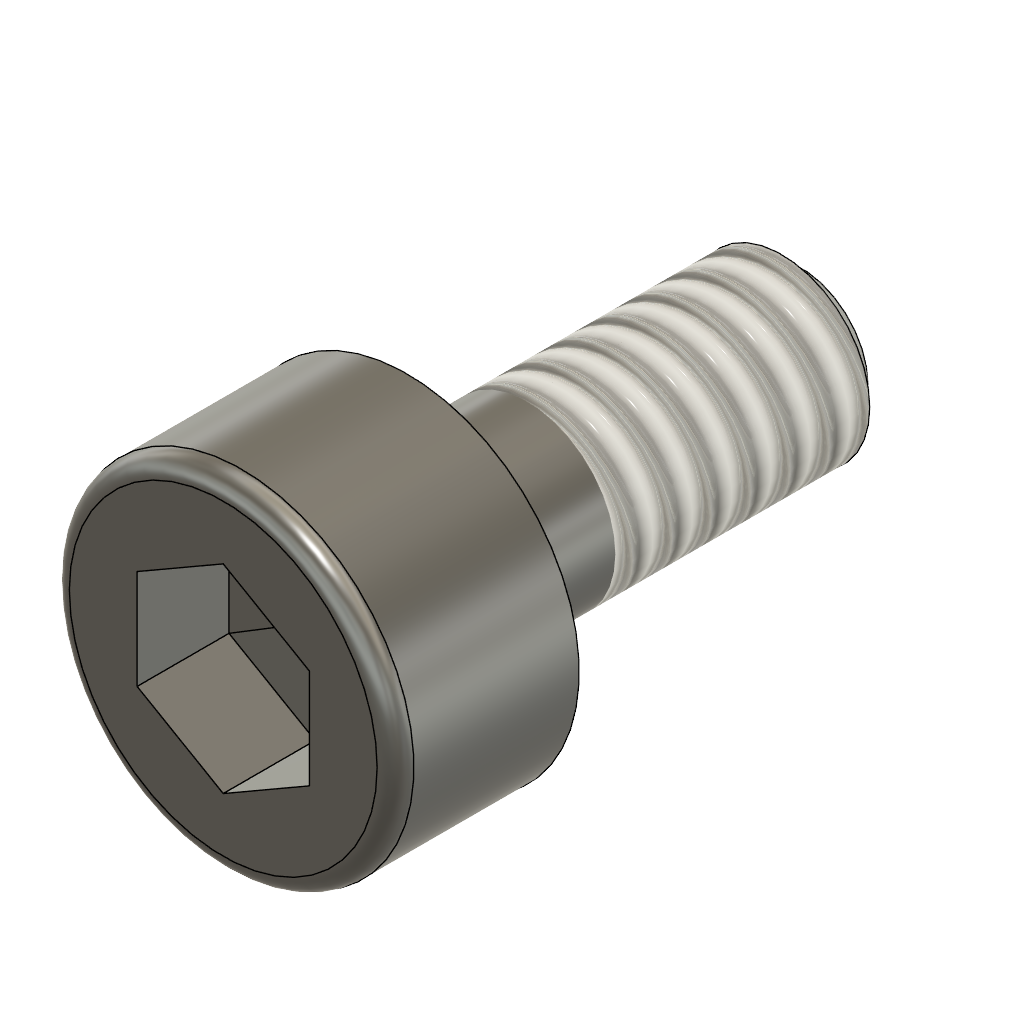
crazy car full (Autodesk Fusion 360 archive; units mm, degrees)
design "Zylinderschraube mit gestanztem Innensechskant ASME B18.3.1M - M1.4x0.3 x 3 Stahlklasse 2 Einfach"
description: Zylinderschraube mit gestanztem Innensechskant ASME B18.3.1M - M1.4x0.3 x 3
part number: BSHCS ASME B18.3.1M - M1.4x0.3 x 3 Stahlklasse 2 Einfach
Autodesk Fusion 360 part; units mm, degrees
sketch "Sketch1" plane through (0, 0, 0) normal (0, 1, 0) x (1, 0, 0)
  line L0 (-0.7, 0) -> (-0.7, 3)
  line L1 (-0.7, 3) -> (0, 3)
  line L2 (0, 3) -> (0, -1.4)
  line L3 (-0.7, 0) -> (-1.3125, 0)
  line L4 (-1.3125, 0) -> (-1.3125, -1.4)
  line L5 (-1.3125, -1.4) -> (0, -1.4)
  dimension "d101" = 3
  dimension "d102" = 1.4
  dimension "d109" = 2.625
  dimension "d110" = 1.4
  constraint perpendicular L0 L1
  constraint collinear origin L1.end L2.end
  constraint perpendicular L0 L3
  constraint coincident origin L3
  constraint vertical L2
  constraint coincident L2 L5.end
  constraint perpendicular L2 L5
  measures "d101" distance of origin L1
  measures "d102" distance of L3.end L5
revolve "Revolve1" add sketch "Sketch1" angle 360 about axis through (0, 0, -3) along (0, 0, 1)
ref_plane "WorkPlane1" through (0, 0, 1.4) normal (0, 0, 1) x (1, 0, 0)
sketch "Sketch6" plane through (0, 0, 1.4) normal (0, 0, 1) x (1, 0, 0)
  line L0 (0, -0.7578) -> (0.6563, -0.3789)
  line L1 (0.6563, -0.3789) -> (0.6563, 0.3789)
  line L2 (0.6563, 0.3789) -> (0, 0.7578)
  line L3 (0, 0.7578) -> (-0.6562, 0.3789)
  line L4 (-0.6562, 0.3789) -> (-0.6563, -0.3789)
  line L5 (-0.6563, -0.3789) -> (0, -0.7578)
  dimension "d111" = 1.3125
  constraint vertical L1
  measures "d111" distance of L1 L4
extrude "Extrude1" cut sketch "Sketch6" against normal blind 0.7
extrude "Extrude2" cut 1 faces at (0, -0.2526, 0.7) along direction (0, 0, -1) blind 0.7 draft -85
thread "Thread3" "ANSI Metric M Profile 1.4 M1.4x0.3 M1.4x0.3 4g6g" major diameter 1.3455 minor diameter 1.0193 pitch 0.3 angle 60 resizes the face on face at (-0.6965, 0.0697, -2) from (0, 0, -0.9147) to (0, 0, -3)
fillet "Fillet4" radius 0.14 1 edges at (-1.2237, 0.4746, 1.4)
sketch "Sketch7" plane through (0, 0, 0) normal (0, 1, 0) x (1, 0, 0)
  line L0 (-0.714, 3) -> (-0.714, 2.816)
  line L1 (-0.714, 2.816) -> (-0.5121, 3)
  line L2 (0, 3) -> (0, -1.4)
  line L3 (-0.714, 3) -> (0, 3)
  dimension "d104" = 0.5121
  dimension "d105" = 0.714
  dimension "d106" = 0.184
  constraint coincident L2.start L3.end
  constraint perpendicular L2 L3
  constraint coincident L1.end L3
  constraint perpendicular L0 L3
  measures "d104" distance of L1.end L2
  measures "d105" distance of L0 L2.start
  measures "d106" distance of L0.end L3
revolve "Revolve3" cut sketch "Sketch7" angle 360 about axis through (0, 0, 1.75) along (0, 0, 1)
equation "adsk_nomlen = 3.00 mm"
equation "adsk_headh = 1.40 mm"
equation "adsk_headdia = 2.625 mm"
equation "adsk_nomdia = 1.40 mm"
equation "adsk_philwidth = 1.3125 mm"
equation "d31 = -adsk_phildepth"
equation "adsk_phildepth = 0.70 mm"
equation "d71 = adsk_headh"
equation "d76 = -adsk_phildepth"
equation "adsk_thrlen = 2.0852925 mm"
equation "d86 = adsk_nomdia * 0.1"
equation "adsk_startlen = 0.184035 mm"
equation "adsk_endpointdia = 1.0242619 mm"
equation "d101 = adsk_nomlen"
equation "d102 = adsk_headh"
equation "d104 = adsk_endpointdia / 2"
equation "d105 = adsk_nomdia * 0.51"
equation "d106 = adsk_startlen"
equation "d108 = min(adsk_thrlen; adsk_nomlen - 0.001 mm)"
equation "d109 = adsk_headdia"
equation "d110 = adsk_nomdia"
equation "d111 = adsk_philwidth"

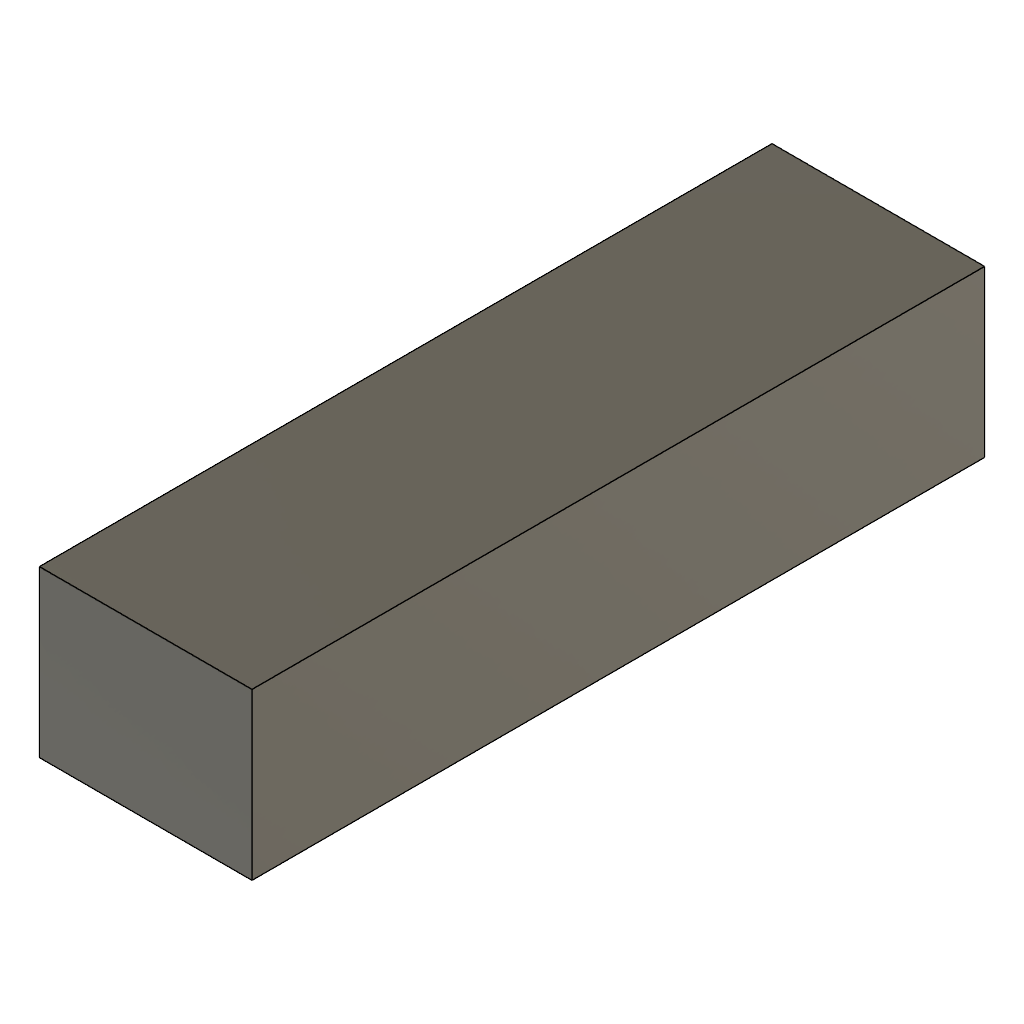
design "Akku"
Autodesk Fusion 360 part; units mm, degrees
sketch "Skizze1" plane through (0, 0, 0) normal (0, 0, 1) x (1, 0, 0)
  line L0 (9, 31) -> (-9, 31)
  line L1 (-9, 31) -> (-9, -31)
  line L2 (-9, -31) -> (9, -31)
  line L3 (9, -31) -> (9, 31)
  line L4 (9, 31) -> (-9, -31) construction
  line L5 (-9, 31) -> (9, -31) construction
  dimension "d1" = 18
  dimension "d2" = 62
  constraint horizontal L0
  constraint perpendicular L0 L1
  constraint parallel L0 L2
  constraint parallel L1 L3
  constraint coincident L4 origin
  constraint coincident L5 origin
  measures "d1" distance of L1.end L2.end
  measures "d2" distance of L0.end L1.end
extrude "Extrusion1" add sketch "Skizze1" along normal blind 14

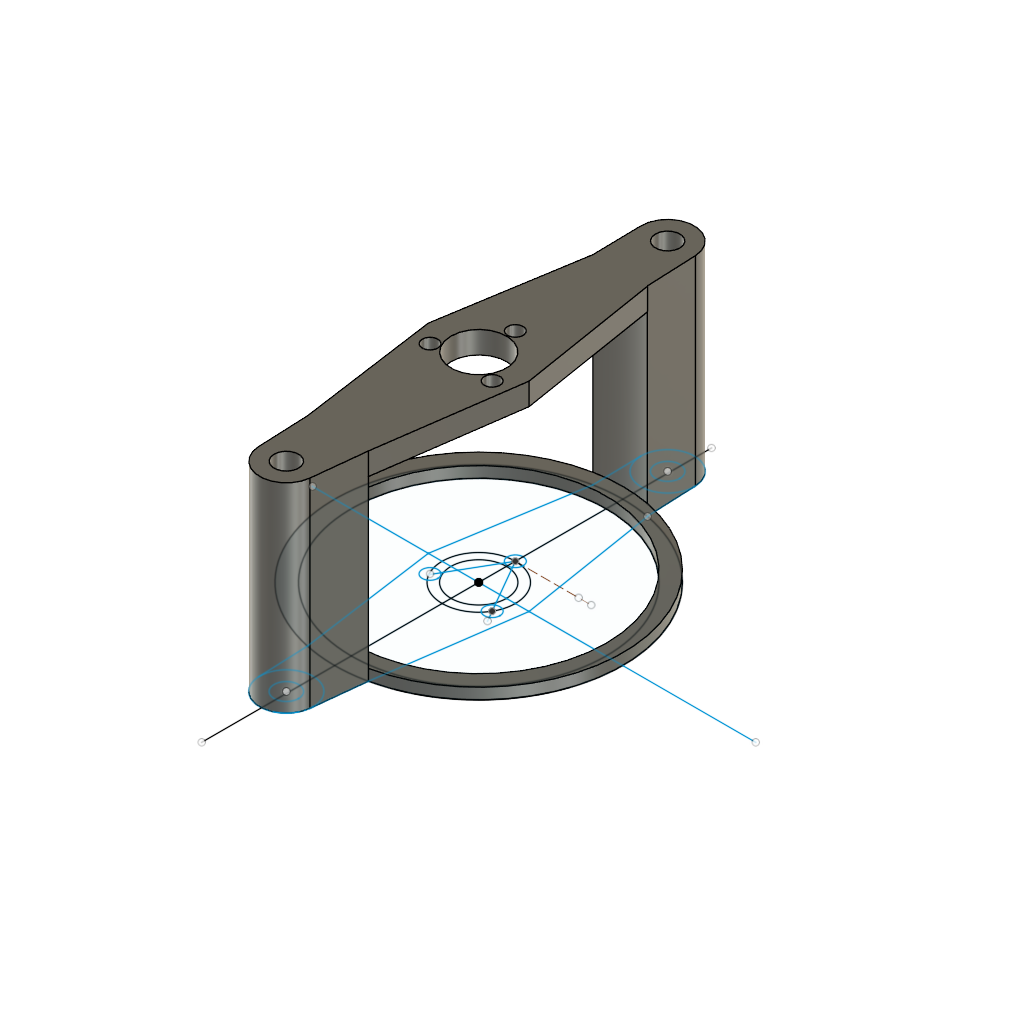
design "impeller halter"
Autodesk Fusion 360 part; units mm, degrees
sketch "Skizze1" plane through (0, 0, 0) normal (0, 0, 1) x (1, 0, 0)
  circle A0 centre (0, 0) radius 13
  circle A1 centre (-0.1535, 17.1993) radius 1.1
  line L0 (-15, -0.0052) -> (25, -0.0052)
  circle A2 centre (-0.1535, -17.2098) radius 1.1
  circle A3 centre (-0.1535, 17.1993) radius 2.4
  circle A4 centre (-0.1535, -17.2098) radius 2.4
  circle A5 centre (0, 0) radius 11.5
  line L1 (-2.5531, 17.1534) -> (-2.469, 12.7634)
  line L2 (2.2442, 17.3039) -> (2.4421, 12.7686)
  line L3 (-2.5512, -17.3144) -> (-2.7523, -12.7053)
  line L4 (2.2323, -17.4701) -> (2.7523, -12.7053)
  circle A6 centre (0, 0) radius 3.3
  circle A7 centre (0, 0) radius 2.5
  circle A8 centre (0, 3.3) radius 0.7
  line L5 (0, 3.3) -> (3.4254, -2.633)
  line L6 (0, 3.3) -> (6.8508, 3.3) construction
  circle A9 centre (2.8579, -1.65) radius 0.7
  line L7 (0, 3.3) -> (-2.8579, -1.65)
  line L8 (0, 3.3) -> (5.7158, 3.3) construction
  circle A10 centre (-2.8579, -1.5392) radius 0.7
  line L9 (-2.469, 12.7634) -> (-4.5435, -0.0052)
  line L10 (-4.5435, -0.0052) -> (-2.7523, -12.7053)
  line L11 (0, 21) -> (0, -25)
  line L12 (2.469, 12.7634) -> (4.5435, -0.0052)
  line L13 (4.5435, -0.0052) -> (2.7523, -12.7053)
  dimension "d1" = 26
  dimension "d2" = 2.2
  dimension "d3" = 17.2
  dimension "d4" = 4.8
  dimension "d5" = 4.8
  dimension "d6" = 23
  dimension "d11" = 6.6
  dimension "d12" = 5
  dimension "d13" = 1.4
  dimension "d14" = 60
  dimension "d15" = 1.4
  dimension "d16" = 120
  dimension "d17" = 1.4
  constraint coincident A0.centre A5.centre
  constraint horizontal L0
  constraint symmetric A1 L0 A2
  constraint concentric A1 A3
  constraint concentric A2 A4
  constraint concentric A0 A5
  constraint coincident A3 L1.start
  constraint coincident A0 L1.end
  constraint tangent A3 L1
  constraint coincident A3 L2.start
  constraint coincident A0 L2.end
  constraint tangent A3 L2
  constraint coincident A0 L3.end
  constraint parallel L2 L3
  constraint coincident A4 L4.start
  constraint coincident A0 L4.end
  constraint tangent A4 L4
  constraint coincident A4 L3.start
  constraint tangent A4 L3
  constraint concentric A0 A6
  constraint coincident A6 A8.centre
  constraint horizontal L6
  constraint coincident A8.centre L5.start
  constraint coincident L5 A9.centre
  constraint coincident A6 A9.centre
  constraint horizontal L8
  constraint coincident A6 L7.end
  constraint coincident L0 L9.end
  constraint vertical L11
  constraint symmetric L1.end L11 L12.start
  constraint symmetric L3.end L4.end L11
  constraint symmetric L9.end L11 L12.end
  measures "d1" diameter of A0
  measures "d2" diameter of A1
  measures "d3" distance of A0.centre A1.centre
  measures "d4" diameter of A3
  measures "d5" diameter of A4
  measures "d6" diameter of A5
  measures "d11" diameter of A6
  measures "d12" diameter of A7
  measures "d13" diameter of A8
  measures "d14" angle of L5 L6
  measures "d15" diameter of A9
  measures "d16" angle of L7 L8
  measures "d17" diameter of A10
extrude "Extrusion1" add sketch "Skizze1" along normal blind 1 contours A0 L0 A5 L12 | A0 A5 L11 L12 | A0 L0 A5 L13 | A0 A5 L11 L13 | A0 A5 L9 L11 | A0 A5 L10 L11 | A0 L0 A5 L9 | A0 L0 A5 L10
extrude "Extrusion2" add sketch "Skizze1" along normal blind 18 contours A0 A3 L2 L11 | A0 A4 L4 L11 | A0 A3 L1 L11 | A1 A3 L11 | A0 A4 L3 L11 | A2 A4 L11 | A1 A3 L11 | A2 A4 L11
extrude "Extrusion3" add sketch "Skizze1" along normal blind 2 from surface at 16 contours A0 A5 L11 L12 | L0 A5 A6 A8 L11 L12 | A0 A5 L11 L13 | A0 A5 L9 L11 | L0 A5 A6 A8 L9 L11 | L0 A5 A6 A9 L11 L13 | A0 A5 L10 L11 | L0 A6 A7 L5 A9 | L0 A6 A7 A8 L5 | L0 A5 A6 A10 L10 L11 | L0 A6 A7 A8 L7 | A6 A7 L5 A9 L11 | A6 A7 L7 A10 L11 | L0 A6 A7 L7 A10 | A7 A8 L7 L11 | A7 A8 L5 L11
equation "d9 = 15 mm + 14 mm - 8 mm - 2 mm - 1 mm"
equation "d18 = 24.00 mm - 8 mm"

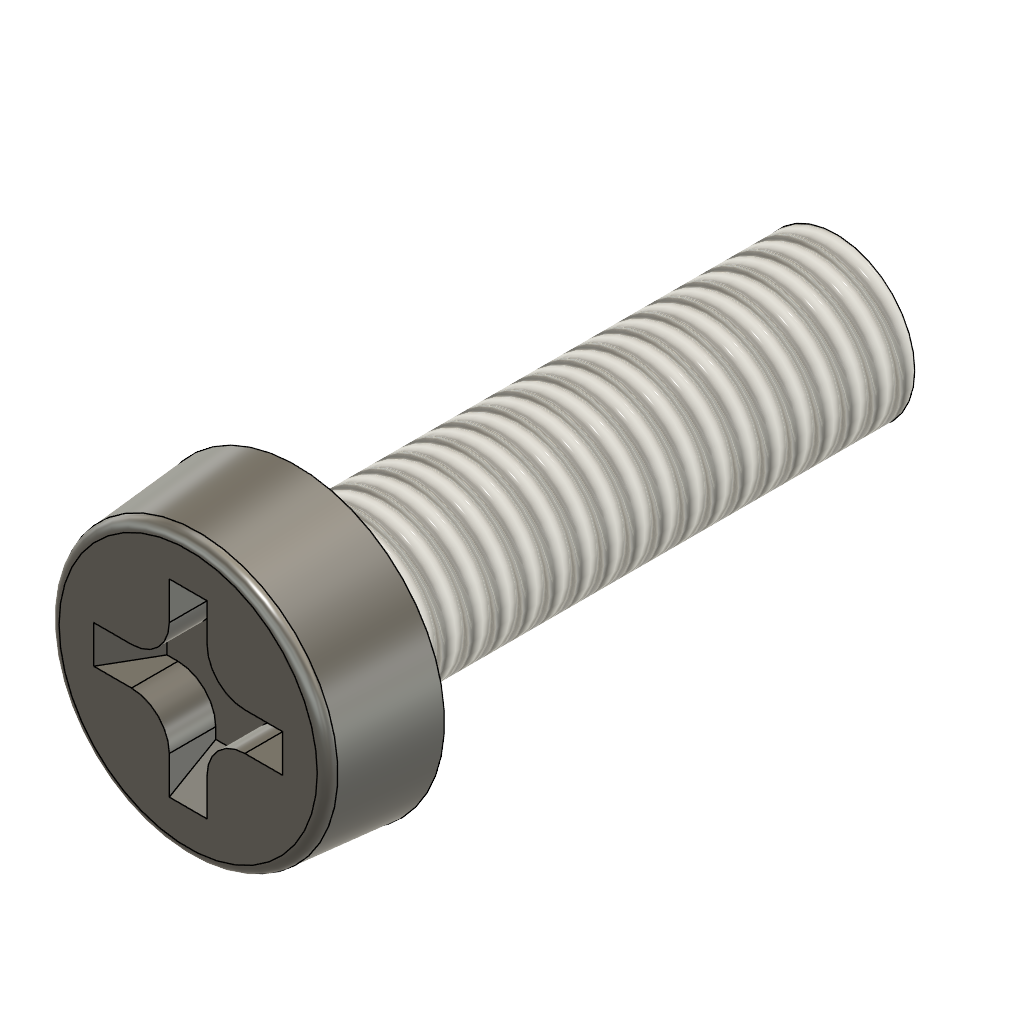
design "Zylinderschraube NS-EN ISO 7048 - M3 x 10 - H Stahl 4.6 Einfach"
description: Zylinderschraube NS-EN ISO 7048 - M3 x 10 - H
part number: NS-EN ISO 7048 - H - M3 x 10 Stahl 4.6 Einfach
Autodesk Fusion 360 part; units mm, degrees
sketch "Sketch1" plane through (0, 0, 0) normal (0, 1, 0) x (1, 0, 0)
  line L0 (0, -2) -> (0, 10)
  line L1 (-2.75, 0) -> (-2.575, -2)
  line L2 (-2.75, 0) -> (-1.325, 0)
  line L3 (0, 10) -> (-1.5, 10)
  line L4 (-1.5, 10) -> (-1.5, 1)
  line L5 (-1.5, 1) -> (-1.325, 0.3469)
  line L6 (-1.325, 0.3469) -> (-1.325, 0)
  line L7 (0, -2) -> (-2.575, -2)
  dimension "d13" = 5
  dimension "d14" = 5.5
  dimension "d18" = 3
  dimension "d56" = 10
  dimension "d65" = 15
  dimension "d67" = 2
  dimension "d71" = 2.65
  dimension "d77" = 1
  constraint vertical L0
  constraint coincident origin L0
  constraint coincident origin L2
  constraint perpendicular L0 L3
  constraint coincident L2.end L6.end
  constraint perpendicular L0 L7
  measures "d13" angle of L0 L1
  measures "d56" distance of L2 L3
  measures "d65" angle of L5 L6
  measures "d67" distance of L1.start L7
  measures "d77" distance of L2 L4.end
revolve "Revolve1" add sketch "Sketch1" angle 360 about axis through (0, 0, 2) along (0, 0, -1) makes body 1
fillet "Fillet3" radius 0.2 1 edges at (-2.4008, 0.9312, 2) on bodies 1
fillet "Fillet2" radius 0.1 1 edges at (-1.2353, 0.4791, 0) on bodies 1
sketch "Sketch2" plane through (0, 0, 2) normal (0, 0, 1) x (1, 0, 0)
  line L0 (-0.35, 0.35) -> (-1.75, 0.35)
  line L1 (-1.75, 0.35) -> (-1.75, -0.35)
  line L2 (-1.75, -0.35) -> (-0.35, -0.35)
  line L3 (-0.35, -0.35) -> (-0.35, -1.75)
  line L4 (-0.35, -1.75) -> (0.35, -1.75)
  line L5 (0.35, -1.75) -> (0.35, -0.35)
  line L6 (0.35, -0.35) -> (1.75, -0.35)
  line L7 (1.75, -0.35) -> (1.75, 0.35)
  line L8 (1.75, 0.35) -> (0.35, 0.35)
  line L9 (0.35, 0.35) -> (0.35, 1.75)
  line L10 (0.35, 1.75) -> (-0.35, 1.75)
  line L11 (-0.35, 1.75) -> (-0.35, 0.35)
  dimension "d81" = 360
  dimension "d83" = 0.7
  dimension "d84" = 3.5
  constraint horizontal L0
  constraint perpendicular L0 L1
  constraint vertical L0.start L2.end
  constraint coincident L2.end L3.start
  measures "d83" distance of L0 L2
  measures "d84" distance of L1 L6.end
extrude "Extrude1" add sketch "Sketch2" against normal blind 0.86 separate body makes body 2
draft "Draft1" angle -30 neutral plane through (0, 0, 2) pull (0, 0, 1) 4 faces at (1.75, -0.1167, 1.7133) (0.1167, 1.75, 1.7133) (-1.75, 0.1167, 1.7133) (-0.1167, -1.75, 1.7133) on bodies 2
fillet "Fillet1" radius 0.7 4 edges at (-0.35, 0.35, 1.57) (-0.35, -0.35, 1.57) (0.35, -0.35, 1.57) (0.35, 0.35, 1.57) on bodies 2
combine "Combine1" operation cut target body 1 tool bodies 2
thread "Thread3" "ISO Metric profile 3.0 M3x0.5 M3x0.5 6g" major diameter 2.927 minor diameter 2.3555 pitch 0.5 angle 60 resizes the face on face at (-1.4981, -0.0748, -7) on bodies 1
equation "adsk_nomdia = 3.00 mm"
equation "adsk_nomlen = 10.00 mm"
equation "adsk_headdia = 5.50 mm"
equation "adsk_phildia = 3.50 mm"
equation "adsk_midfillet = 0.10 mm"
equation "adsk_phildepth = 0.86 mm"
equation "adsk_shnklen = 1.00 mm"
equation "adsk_thrang = 15 deg"
equation "adsk_headang = 5 deg"
equation "d13 = adsk_headang"
equation "d14 = adsk_headdia"
equation "d18 = adsk_nomdia"
equation "adsk_philwidth = 0.70 mm"
equation "d43 = -adsk_phildepth"
equation "d52 = adsk_midfillet"
equation "d56 = adsk_nomlen"
equation "d65 = adsk_thrang"
equation "d67 = adsk_headh"
equation "adsk_headh = 2.00 mm"
equation "adsk_pitch1 = 0.50 mm"
equation "adsk_shnkdia = adsk_nomdia - 0.7 * adsk_pitch1"
equation "d71 = adsk_shnkdia"
equation "adsk_headtoprad = adsk_headh * 0.1"
equation "d76 = adsk_headtoprad"
equation "d77 = adsk_shnklen"
equation "d83 = adsk_philwidth"
equation "d84 = adsk_phildia"
equation "d86 = adsk_philwidth"

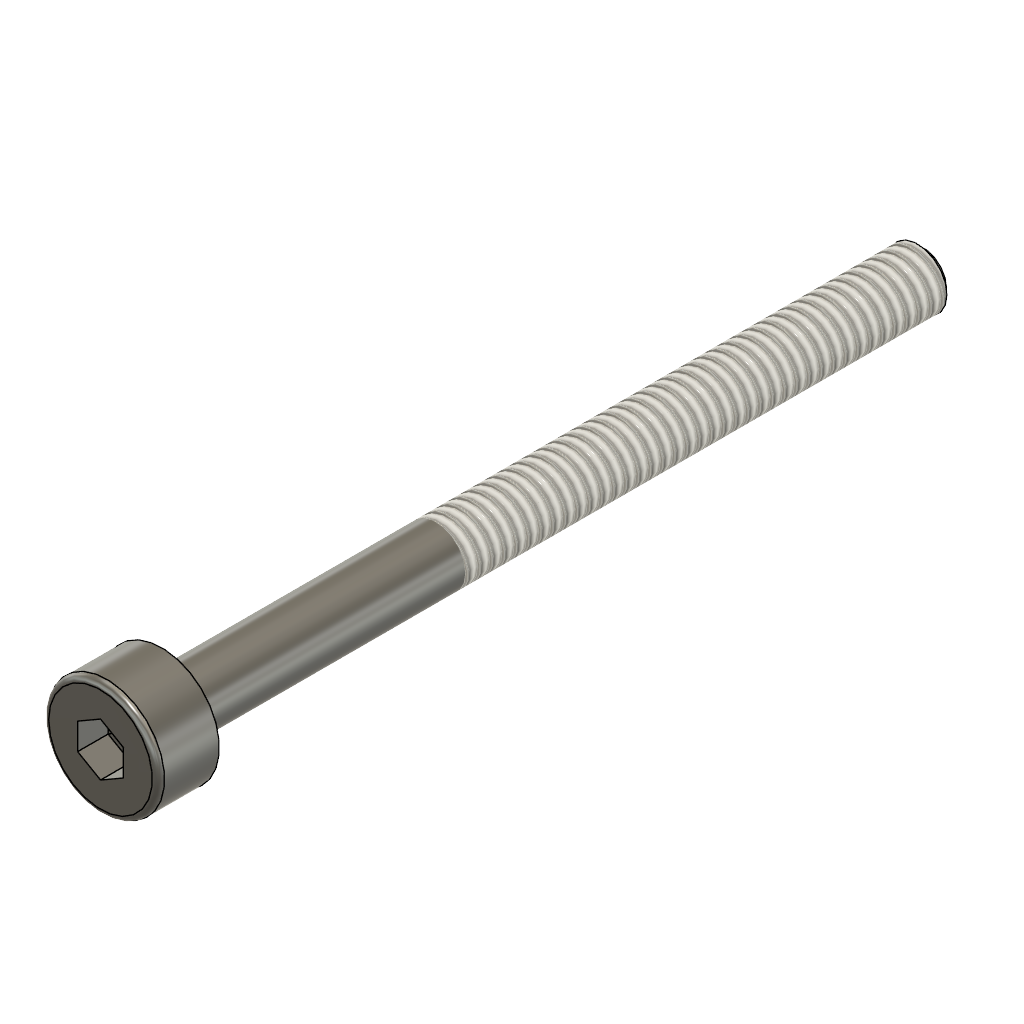
design "Zylinderschraube mit gestanztem Innensechskant ASME B18.3.1M - M2x0.4 x 25 Stahlklasse 2 Einfach"
description: Zylinderschraube mit gestanztem Innensechskant ASME B18.3.1M - M2x0.4 x 25
part number: BSHCS ASME B18.3.1M - M2x0.4 x 25 Stahlklasse 2 Einfach
Autodesk Fusion 360 part; units mm, degrees
sketch "Sketch1" plane through (0, 0, 0) normal (0, 1, 0) x (1, 0, 0)
  line L0 (-1, 0) -> (-1, 25)
  line L1 (-1, 25) -> (0, 25)
  line L2 (0, 25) -> (0, -2)
  line L3 (-1, 0) -> (-1.9, 0)
  line L4 (-1.9, 0) -> (-1.9, -2)
  line L5 (-1.9, -2) -> (0, -2)
  dimension "d101" = 25
  dimension "d102" = 2
  dimension "d109" = 3.8
  dimension "d110" = 2
  constraint perpendicular L0 L1
  constraint collinear origin L1.end L2.end
  constraint perpendicular L0 L3
  constraint coincident origin L3
  constraint vertical L2
  constraint coincident L2 L5.end
  constraint perpendicular L2 L5
  measures "d101" distance of origin L1
  measures "d102" distance of L3.end L5
revolve "Revolve1" add sketch "Sketch1" angle 360 about axis through (0, 0, -25) along (0, 0, 1)
ref_plane "WorkPlane1" through (0, 0, 2) normal (0, 0, 1) x (1, 0, 0)
sketch "Sketch6" plane through (0, 0, 2) normal (0, 0, 1) x (1, 0, 0)
  line L0 (0, -0.866) -> (0.75, -0.433)
  line L1 (0.75, -0.433) -> (0.75, 0.433)
  line L2 (0.75, 0.433) -> (0, 0.866)
  line L3 (0, 0.866) -> (-0.75, 0.433)
  line L4 (-0.75, 0.433) -> (-0.75, -0.433)
  line L5 (-0.75, -0.433) -> (0, -0.866)
  dimension "d111" = 1.5
  constraint vertical L1
  measures "d111" distance of L1 L4
extrude "Extrude1" cut sketch "Sketch6" against normal blind 1
extrude "Extrude2" cut 1 faces at (0, -0.2887, 1) along direction (0, 0, -1) blind 1 draft -85
thread "Thread3" "ANSI Metric M Profile 2.0 M2x0.4 M2x0.4 4g6g" major diameter 1.9335 minor diameter 1.4905 pitch 0.4 angle 60 resizes the face on face at (-0.995, 0.0996, -16.6667) from (0, 0, -9) to (0, 0, -25)
fillet "Fillet4" radius 0.2 1 edges at (-1.7714, 0.6871, 2)
sketch "Sketch7" plane through (0, 0, 0) normal (0, 1, 0) x (1, 0, 0)
  line L0 (-1.02, 25) -> (-1.02, 24.7546)
  line L1 (-1.02, 24.7546) -> (-0.7546, 25)
  line L2 (0, 25) -> (0, -2)
  line L3 (-1.02, 25) -> (0, 25)
  dimension "d104" = 0.7546
  dimension "d105" = 1.02
  dimension "d106" = 0.2454
  constraint coincident L2.start L3.end
  constraint perpendicular L2 L3
  constraint coincident L1.end L3
  constraint perpendicular L0 L3
  measures "d104" distance of L1.end L2
  measures "d105" distance of L0 L2.start
  measures "d106" distance of L0.end L3
revolve "Revolve3" cut sketch "Sketch7" angle 360 about axis through (0, 0, 1.75) along (0, 0, 1)
equation "adsk_nomlen = 25.00 mm"
equation "adsk_headh = 2.00 mm"
equation "adsk_headdia = 3.80 mm"
equation "adsk_nomdia = 2.00 mm"
equation "adsk_philwidth = 1.50 mm"
equation "d31 = -adsk_phildepth"
equation "adsk_phildepth = 1.00 mm"
equation "d71 = adsk_headh"
equation "d76 = -adsk_phildepth"
equation "adsk_thrlen = 16.00 mm"
equation "d86 = adsk_nomdia * 0.1"
equation "adsk_startlen = 0.24538 mm"
equation "adsk_endpointdia = 1.50924 mm"
equation "d101 = adsk_nomlen"
equation "d102 = adsk_headh"
equation "d104 = adsk_endpointdia / 2"
equation "d105 = adsk_nomdia * 0.51"
equation "d106 = adsk_startlen"
equation "d108 = min(adsk_thrlen; adsk_nomlen - 0.001 mm)"
equation "d109 = adsk_headdia"
equation "d110 = adsk_nomdia"
equation "d111 = adsk_philwidth"

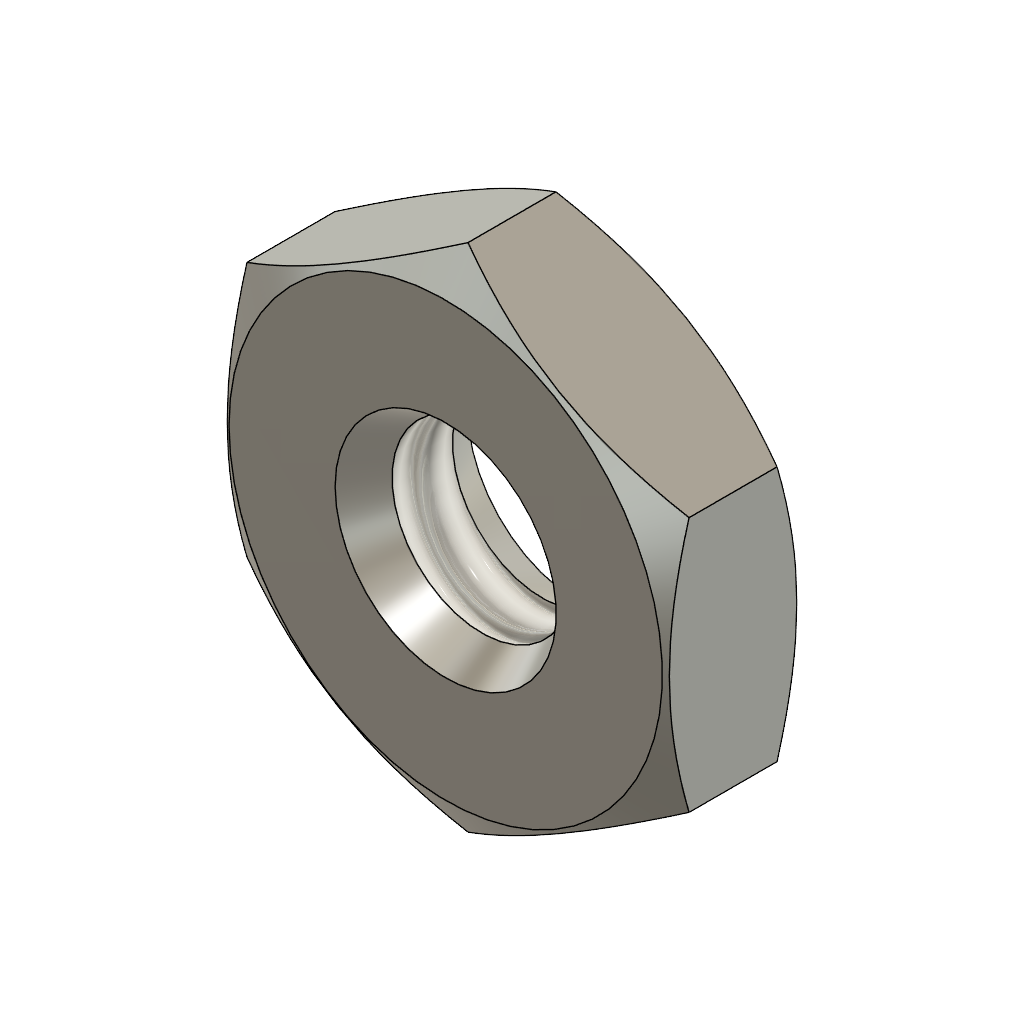
design "Sechskantmutter - niedrige Form DIN 439-2 - M2 x 0.4 Stahl 6 Einfach"
description: Sechskantmutter - niedrige Form DIN 439-2 - M2 x 0.4
part number: DIN 439-2 - M2 x 0.4 Stahl 6 Einfach
Autodesk Fusion 360 part; units mm, degrees
sketch "Sketch1" plane through (0, 0, 0) normal (0, 1, 0) x (1, 0, 0)
  line L0 (0, 0) -> (0, -1.2)
  line L1 (-1, 0) -> (-1.96, 0)
  line L2 (-1.96, 0) -> (-2.31, -0.2021)
  line L3 (-2.31, -0.2021) -> (-2.31, -0.9979)
  line L4 (-2.31, -0.9979) -> (-1.96, -1.2)
  line L5 (-1.96, -1.2) -> (-1, -1.2)
  line L6 (-1, -1.2) -> (-1, 0)
  dimension "d121" = 2
  dimension "d122" = 30
  dimension "d123" = 30
  dimension "d128" = 4.62
  dimension "d172" = 3.92
  dimension "d179" = 1.2
  constraint vertical L0
  constraint coincident L0 L0.end
  constraint coincident origin L0
  constraint horizontal L1
  constraint coincident L0.start L1
  constraint coincident L0.start origin
  constraint coincident L0.end L5
  constraint vertical L1.end L4.end
  measures "d122" angle of L1 L2
  measures "d123" angle of L4 L5
  measures "d179" distance of L1 L5
revolve "Revolve1" add sketch "Sketch1" angle 360 about axis through (0, 0, 0) along (0, 0, 1)
sketch "Sketch8" plane through (0, 0, 1.2) normal (0, 0, 1) x (1, 0, 0)
  line L0 (-2, -1.1559) -> (-2, 1.1559)
  circle A0 centre (0, 0) radius 1
  circle A1 centre (0, 0) radius 2.31
  dimension "d114" = 2
  constraint coincident L0.end A1
  constraint coincident L0.start A1
  constraint vertical L0
  measures "d114" distance of A0.centre L0
extrude "Extrude5" cut sketch "Sketch8" against normal blind 1.2 contours L0 A1 picked at (-2.05, 0.2815)
pattern_circular "C-Pattern2" count 6 over 360 about axis through (0, 0, 1.75) along (0, 0, 1) of "Extrude5"
thread "Thread3" "ISO Metric profile 2.0 M2x0.4 M2x0.4 6H" major diameter 2.074 minor diameter 1.623 pitch 0.4 angle 60 resizes the face on face at (-0.995, 0.0996, 0.8)
sketch "Sketch12" plane through (0, 0, 0) normal (0, 1, 0) x (1, 0, 0)
  line L0 (-1, 0) -> (0, 0)
  line L1 (-0.6536, -0.6) -> (-1, 0)
  line L2 (-1, -1.2) -> (0, -1.2)
  line L3 (-0.6536, -0.6) -> (-1, -1.2)
  line L4 (0, 0) -> (0, -1.2)
  dimension "d169" = 60
  dimension "d177" = 1
  dimension "d178" = 60
  constraint horizontal L0
  constraint coincident L1.start L3.start
  constraint vertical L0.start L2.start
  constraint coincident L2.end L4.end
  constraint coincident L0.end L4.start
  constraint perpendicular L2 L4
  measures "d169" angle of L2 L3
  measures "d177" distance of L0.start L4
  measures "d178" angle of L0 L1
revolve "Revolve3" cut sketch "Sketch12" angle 360 about axis through (0, 0, 1.75) along (0, 0, 1)
equation "adsk_nheig = 1.20 mm"
equation "adsk_maxdia = 4.62 mm"
equation "adsk_nomdia = 2.00 mm"
equation "d89 = -adsk_nheig"
equation "adsk_waflat = 4.00 mm"
equation "d114 = adsk_waflat / 2"
equation "adsk_chamang1 = 30.00 deg"
equation "adsk_chamang2 = 30.00 deg"
equation "d121 = adsk_nomdia"
equation "d122 = adsk_chamang1"
equation "d123 = adsk_chamang2"
equation "d128 = adsk_maxdia"
equation "d163 = adsk_nheig"
equation "adsk_beardia = 3.92 mm"
equation "d172 = adsk_beardia"
equation "d177 = adsk_nomdia * 0.5"
equation "d179 = adsk_nheig"

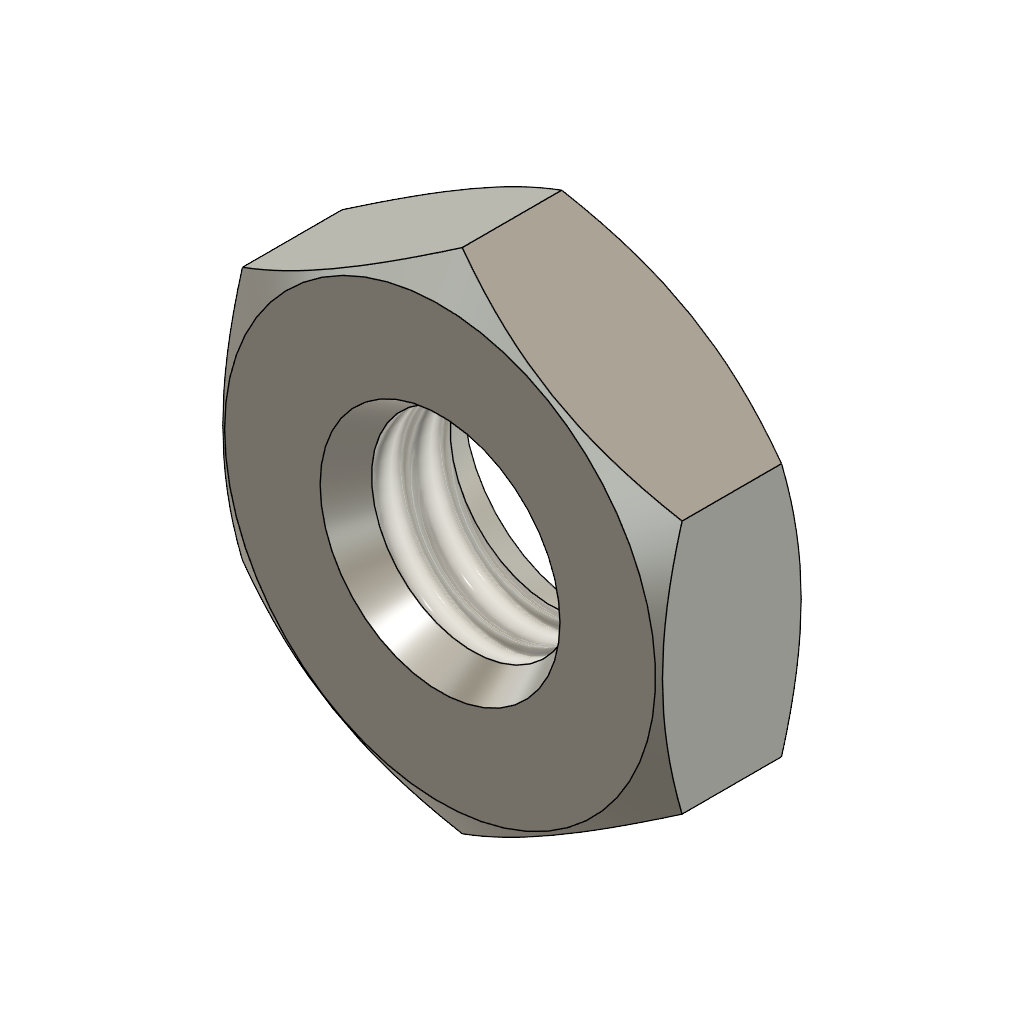
design "Sechskantmutter - niedrige Form DIN 439-2 - M3 x 0.5 Stahl 6 Einfach"
description: Sechskantmutter - niedrige Form DIN 439-2 - M3 x 0.5
part number: DIN 439-2 - M3 x 0.5 Stahl 6 Einfach
Autodesk Fusion 360 part; units mm, degrees
sketch "Sketch1" plane through (0, 0, 0) normal (0, 1, 0) x (1, 0, 0)
  line L0 (0, 0) -> (0, -1.8)
  line L1 (-1.5, 0) -> (-2.695, 0)
  line L2 (-2.695, 0) -> (-3.1763, -0.2778)
  line L3 (-3.1763, -0.2778) -> (-3.1763, -1.5222)
  line L4 (-3.1763, -1.5222) -> (-2.695, -1.8)
  line L5 (-2.695, -1.8) -> (-1.5, -1.8)
  line L6 (-1.5, -1.8) -> (-1.5, 0)
  dimension "d121" = 3
  dimension "d122" = 30
  dimension "d123" = 30
  dimension "d128" = 6.3525
  dimension "d172" = 5.39
  dimension "d179" = 1.8
  constraint vertical L0
  constraint coincident L0 L0.end
  constraint coincident origin L0
  constraint horizontal L1
  constraint coincident L0.start L1
  constraint coincident L0.start origin
  constraint coincident L0.end L5
  constraint vertical L1.end L4.end
  measures "d122" angle of L1 L2
  measures "d123" angle of L4 L5
  measures "d179" distance of L1 L5
revolve "Revolve1" add sketch "Sketch1" angle 360 about axis through (0, 0, 0) along (0, 0, 1)
sketch "Sketch8" plane through (0, 0, 1.8) normal (0, 0, 1) x (1, 0, 0)
  line L0 (-2.75, -1.5894) -> (-2.75, 1.5894)
  circle A0 centre (0, 0) radius 1.5
  circle A1 centre (0, 0) radius 3.1763
  dimension "d114" = 2.75
  constraint coincident L0.end A1
  constraint coincident L0.start A1
  constraint vertical L0
  measures "d114" distance of A0.centre L0
extrude "Extrude5" cut sketch "Sketch8" against normal blind 1.8 contours L0 A1 picked at (-2.8188, -0.3871)
pattern_circular "C-Pattern2" count 6 over 360 about axis through (0, 0, 1.75) along (0, 0, 1) of "Extrude5"
thread "Thread3" "ISO Metric profile 3.0 M3x0.5 M3x0.5 6H" major diameter 3.086 minor diameter 2.529 pitch 0.5 angle 60 resizes the face on face at (-1.4981, 0.0748, 1.2)
sketch "Sketch12" plane through (0, 0, 0) normal (0, 1, 0) x (1, 0, 0)
  line L0 (-1.5, 0) -> (0, 0)
  line L1 (-0.9804, -0.9) -> (-1.5, 0)
  line L2 (-1.5, -1.8) -> (0, -1.8)
  line L3 (-0.9804, -0.9) -> (-1.5, -1.8)
  line L4 (0, 0) -> (0, -1.8)
  dimension "d169" = 60
  dimension "d177" = 1.5
  dimension "d178" = 60
  constraint horizontal L0
  constraint coincident L1.start L3.start
  constraint vertical L0.start L2.start
  constraint coincident L2.end L4.end
  constraint coincident L0.end L4.start
  constraint perpendicular L2 L4
  measures "d169" angle of L2 L3
  measures "d177" distance of L0.start L4
  measures "d178" angle of L0 L1
revolve "Revolve3" cut sketch "Sketch12" angle 360 about axis through (0, 0, 1.75) along (0, 0, 1)
equation "adsk_nheig = 1.80 mm"
equation "adsk_maxdia = 6.3525 mm"
equation "adsk_nomdia = 3.00 mm"
equation "d89 = -adsk_nheig"
equation "adsk_waflat = 5.50 mm"
equation "d114 = adsk_waflat / 2"
equation "adsk_chamang1 = 30.00 deg"
equation "adsk_chamang2 = 30.00 deg"
equation "d121 = adsk_nomdia"
equation "d122 = adsk_chamang1"
equation "d123 = adsk_chamang2"
equation "d128 = adsk_maxdia"
equation "d163 = adsk_nheig"
equation "adsk_beardia = 5.39 mm"
equation "d172 = adsk_beardia"
equation "d177 = adsk_nomdia * 0.5"
equation "d179 = adsk_nheig"

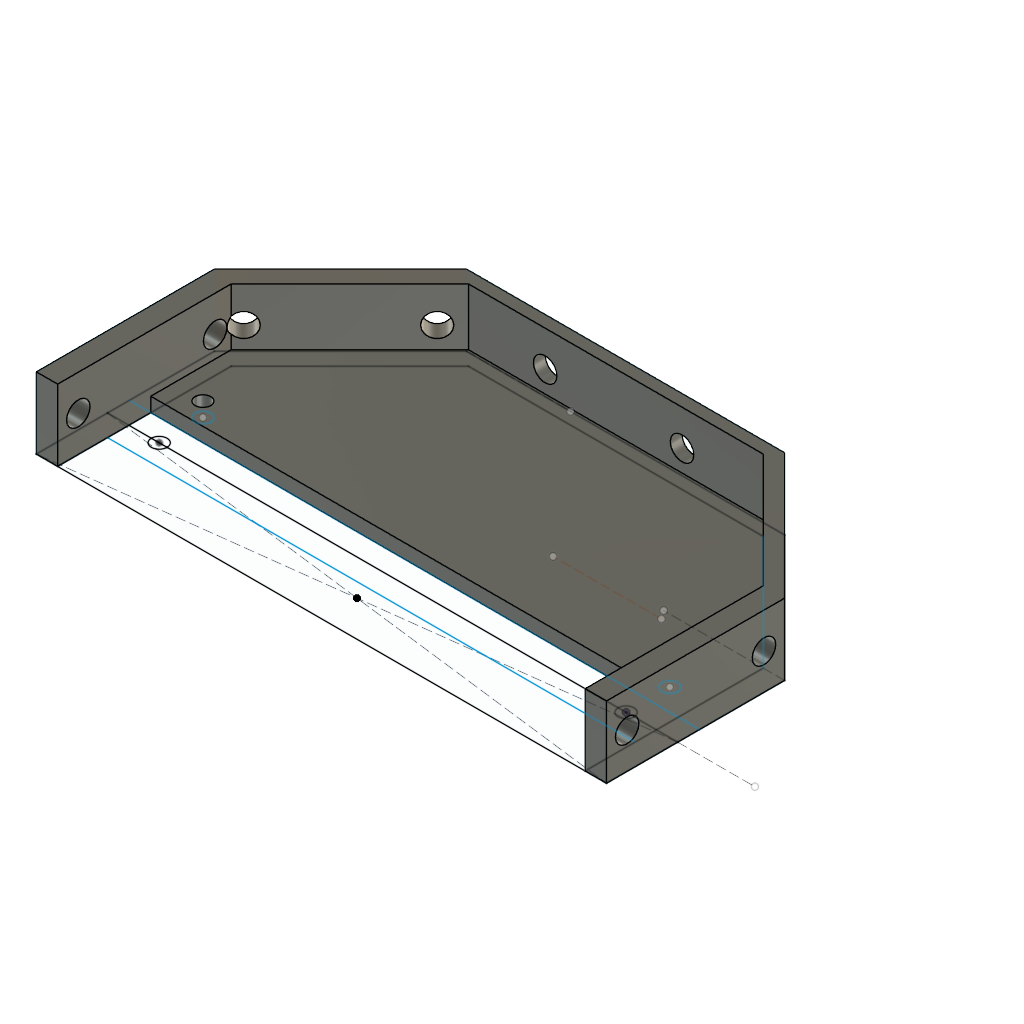
design "holdersensor"
Autodesk Fusion 360 part; units mm, degrees
sketch "Skizze1" plane through (0, 0, 0) normal (0, 0, 1) x (1, 0, 0)
  circle A0 centre (-65.5, 0) radius 1.1
  circle A1 centre (0, 0) radius 1.1
  line L0 (7.25, 0) -> (-72.75, 0)
  line L1 (-72.75, 0) -> (-72.75, -10)
  line L2 (-72.75, -10) -> (7.25, -10)
  line L3 (7.25, -10) -> (7.25, 0)
  line L4 (7.25, 0) -> (-72.75, -10) construction
  line L5 (-72.75, 0) -> (7.25, -10) construction
  line L6 (7.25, 0) -> (18.0731, 0) construction
  line L7 (-8.8647, 13.8168) -> (-24.0621, 13.8168) construction
  line L8 (7.25, 0) -> (7.25, 15)
  line L9 (7.25, 15) -> (-10.4277, 32.6777)
  line L10 (7.25, 15) -> (-9.7271, 15) construction
  line L11 (-10.4277, 32.6777) -> (-55.0723, 32.6777)
  line L12 (-55.0723, 32.6777) -> (-72.75, 15)
  line L13 (-55.0723, 32.6777) -> (-40.4551, 32.6777) construction
  line L14 (-72.75, 0) -> (-72.75, 15)
  line L15 (4.25, -10) -> (4.25, 15)
  line L16 (4.25, 15) -> (-11.7485, 30.9985)
  line L17 (-69.75, -10) -> (-69.75, 14.3513)
  line L18 (-69.75, 14.3513) -> (-53.1029, 30.9985)
  line L19 (-53.1029, 30.9985) -> (-11.7485, 30.9985)
  line L20 (4.25, -3) -> (-69.75, -3)
  line L21 (-72.75, 3.0669) -> (7.25, 3.0669)
  circle A2 centre (-65.5, 6.1339) radius 1.1
  circle A3 centre (0, 6.1339) radius 1.1
  point P0 (-32.75, -5)
  dimension "d1" = 2.2
  dimension "d2" = 2.2
  dimension "d3" = 65.5
  dimension "d12" = 45
  dimension "d13" = 25
  dimension "d15" = 45
  dimension "d16" = 25
  dimension "d18" = 80
  dimension "d20" = 90
  dimension "d21" = 25
  dimension "d22" = 7.25
  dimension "d53" = 10
  dimension "d55" = 1.6792
  dimension "d56" = 30.9985
  dimension "d61" = 180
  dimension "d63" = 2.58
  dimension "d64" = 3
  dimension "d65" = 3
  dimension "d66" = 10
  constraint coincident A1.centre origin
  constraint horizontal L0
  constraint perpendicular L0 L1
  constraint parallel L0 L2
  constraint parallel L1 L3
  constraint coincident L4 P0
  constraint coincident L5 P0
  constraint horizontal L6
  constraint horizontal L7
  constraint perpendicular L0 L8
  constraint horizontal L10
  constraint horizontal L11
  constraint horizontal L13
  constraint coincident L2 L15.start
  constraint coincident L10 L15.end
  constraint perpendicular L10 L15
  constraint coincident L2 L17.start
  constraint perpendicular L2 L17
  constraint horizontal L19
  constraint coincident L15 L20.start
  constraint coincident L17 L20.end
  constraint perpendicular L17 L20
  constraint coincident L14 L21.start
  constraint coincident L8 L21.end
  constraint perpendicular L8 L21
  constraint symmetric A0 L21 A2
  constraint symmetric A1 L21 A3
  measures "d1" diameter of A0
  measures "d2" diameter of A1
  measures "d3" distance of A1.centre A0.centre
  measures "d12" angle of L9 L10
  measures "d13" distance of L8.end L9.end
  measures "d15" angle of L12 L13
  measures "d16" distance of L11.end L12.end
  measures "d18" distance of L1.end L2.end
  measures "d20" angle of L0 L14
  measures "d21" distance of L2.end L8.end
  measures "d22" distance of A0.centre L1
  measures "d53" distance of A0.centre L2
  measures "d55" distance of L11 L19
  measures "d56" distance of L0 L19
  measures "d61" angle of L12 L18
  measures "d63" distance of L12 L18
  measures "d64" distance of L14 L17
  measures "d65" distance of L8 L15
  measures "d66" distance of A1.centre L2
extrude "Extrusion1" add sketch "Skizze1" along normal blind 10 contours A0 A1 L0 L15 L17 L20 | L0 L1 L2 L17 | L2 L15 L17 L20 | L0 L2 L3 L15
extrude "Extrusion2" add sketch "Skizze1" along normal blind 10 contours A0 L0 | A0 A1 L0 L15 L17 L21 | A1 L0 | L0 L14 L17 L21 | L8 L9 L11 L12 L14 L15 L16 L17 L18 L19 L21 | L15 L16 L17 L18 L19 L21 | L0 L8 L15 L21 | A2 | A3 picked at (-65.801, 0.4631) picked at (0.2688, 0.2494)
sketch "Skizze3" plane through (7.25, 0, 0) normal (1, 0, 0) x (0, 1, 0)
  line L0 (-10, 0) -> (15, 0)
  line L1 (15, 0) -> (15, 10)
  line L2 (15, 10) -> (-10, 10)
  line L3 (-10, 10) -> (-10, 0)
  circle A0 centre (-7.1, 5) radius 1.65
  circle A1 centre (12.1, 5) radius 1.65
  dimension "d25" = 3.3
  dimension "d26" = 3.3
  dimension "d27" = 19.2
  dimension "d28" = 2.9
  measures "d25" diameter of A0
  measures "d26" diameter of A1
  measures "d27" distance of A0.centre A1.centre
  measures "d28" distance of L1 A1.centre
sketch "Skizze4" plane through (11.125, 11.125, 0) normal (0.707107, 0.707107, 0) x (-0.707107, 0.707107, 0)
  line L0 (5.4801, 0) -> (30.4801, 0)
  line L1 (30.4801, 0) -> (30.4801, 10)
  line L2 (30.4801, 10) -> (5.4801, 10)
  line L3 (5.4801, 10) -> (5.4801, 0)
  circle A0 centre (8.3801, 5) radius 1.65
  circle A1 centre (27.5801, 5) radius 1.65
  dimension "d29" = 3.3
  dimension "d30" = 3.3
  dimension "d31" = 19.2
  dimension "d71" = 2.9
  measures "d29" diameter of A0
  measures "d30" diameter of A1
  measures "d31" distance of A0.centre A1.centre
  measures "d71" distance of L3 A0.centre
sketch "Skizze5" plane through (0, 32.6777, 0) normal (0, 1, 0) x (-1, 0, 0)
  line L0 (10.4277, 0) -> (55.0723, 0)
  line L1 (55.0723, 0) -> (55.0723, 10)
  line L2 (55.0723, 10) -> (10.4277, 10)
  line L3 (10.4277, 10) -> (10.4277, 0)
sketch "Skizze6" plane through (0, 32.6777, 0) normal (0, 1, 0) x (-1, 0, 0)
  circle A0 centre (23.15, 5) radius 1.65
  circle A1 centre (42.35, 5) radius 1.65
  line L0 (10.4277, 0) -> (55.0723, 0)
  line L1 (10.4277, 10) -> (10.4277, 0)
  line L2 (55.0723, 0) -> (55.0723, 10)
  dimension "d32" = 3.3
  dimension "d33" = 3.3
  dimension "d34" = 19.2
  dimension "d35" = 44.6447
  dimension "d37" = 12.7223
  measures "d32" diameter of A0
  measures "d33" diameter of A1
  measures "d34" distance of A0.centre A1.centre
  measures "d35" distance of L0.start L0.end
  measures "d37" distance of A1.centre L2
sketch "Skizze7" plane through (-43.875, 43.875, 0) normal (-0.707107, 0.707107, 0) x (-0.707107, -0.707107, 0)
  line L0 (15.8354, 0) -> (40.8354, 0)
  line L1 (40.8354, 0) -> (40.8354, 10)
  line L2 (40.8354, 10) -> (15.8354, 10)
  line L3 (15.8354, 10) -> (15.8354, 0)
  circle A0 centre (18.7354, 5) radius 1.65
  circle A1 centre (37.9354, 5) radius 1.65
  line L4 (15.8354, 0) -> (15.8354, 10)
  dimension "d38" = 3.3
  dimension "d39" = 3.3
  dimension "d40" = 19.2
  dimension "d41" = 2.9
  measures "d38" diameter of A0
  measures "d39" diameter of A1
  measures "d40" distance of A0.centre A1.centre
  measures "d41" distance of A0.centre L4
sketch "Skizze8" plane through (-72.75, 0, 0) normal (-1, 0, 0) x (0, -1, 0)
  line L0 (-15, 0) -> (10, 0)
  line L1 (10, 0) -> (10, 10)
  line L2 (10, 10) -> (-15, 10)
  line L3 (-15, 10) -> (-15, 0)
sketch "Skizze9" plane through (-72.75, 0, 0) normal (-1, 0, 0) x (0, -1, 0)
extrude "Extrusion3" cut sketch "Skizze1" along normal blind 1000 from surface at 2 contours A0 L0 | A0 A1 L0 L15 L17 L20 | A0 A1 L0 L15 L17 L21 | A0 L0 | A1 L0 | A1 L0 | L15 L16 L17 L18 L19 L21 | A2 | A3
extrude "Extrusion4" cut sketch "Skizze7" against normal blind 10 contours A0 | A1
extrude "Extrusion5" cut sketch "Skizze6" against normal blind 10
extrude "Extrusion6" cut sketch "Skizze4" against normal blind 10 contours A0 | A1
extrude "Extrusion7" cut sketch "Skizze3" against normal blind 1000 contours A0 | A1
extrude "Extrusion8" cut sketch "Skizze1" along normal blind 100 contours L2 L15 L17 L20
extrude "Extrusion9" cut sketch "Skizze1" along normal blind 1000 contours A2 | A3
extrude "Extrusion10" cut sketch "Skizze1" along normal blind 100 contours A0 L0 | A0 A1 L0 L15 L17 L20 | A0 A1 L0 L15 L17 L21 | A0 L0 | A1 L0 | A1 L0
equation "d22 = ( d18 - d3 ) / 2"
equation "d28 = ( 25 mm - d27 ) / 2"
equation "d37 = ( d35 - 19.2 mm ) / 2"
equation "d41 = ( 25 mm - d40 ) / 2"
equation "d71 = ( 25 mm - 19.2 mm ) / 2"

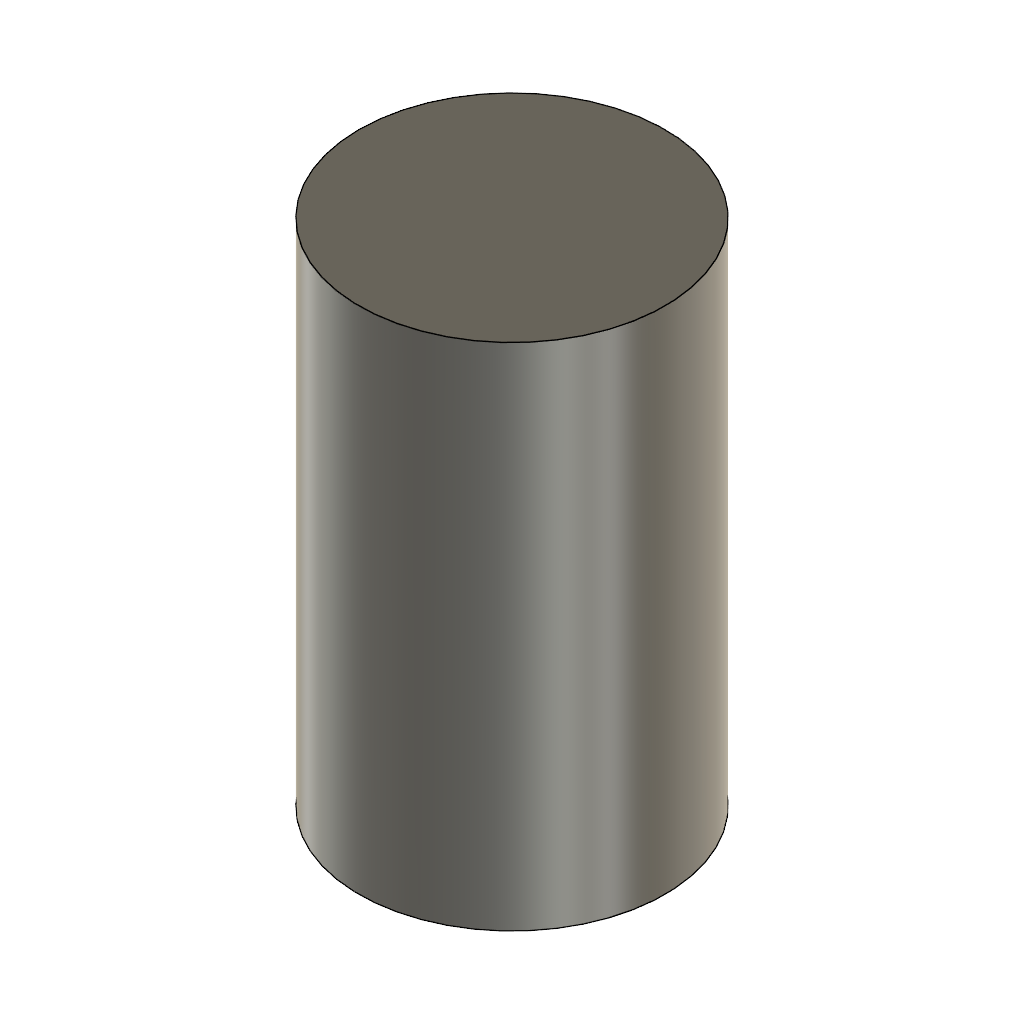
design "plug"
Autodesk Fusion 360 part; units mm, degrees
sketch "Skizze1" plane through (0, 0, 0) normal (0, 0, 1) x (1, 0, 0)
  circle A0 centre (0, 0) radius 1.5
  dimension "d1" = 3
  constraint coincident A0.centre origin
  measures "d1" diameter of A0
extrude "Extrusion1" add sketch "Skizze1" along normal blind 5

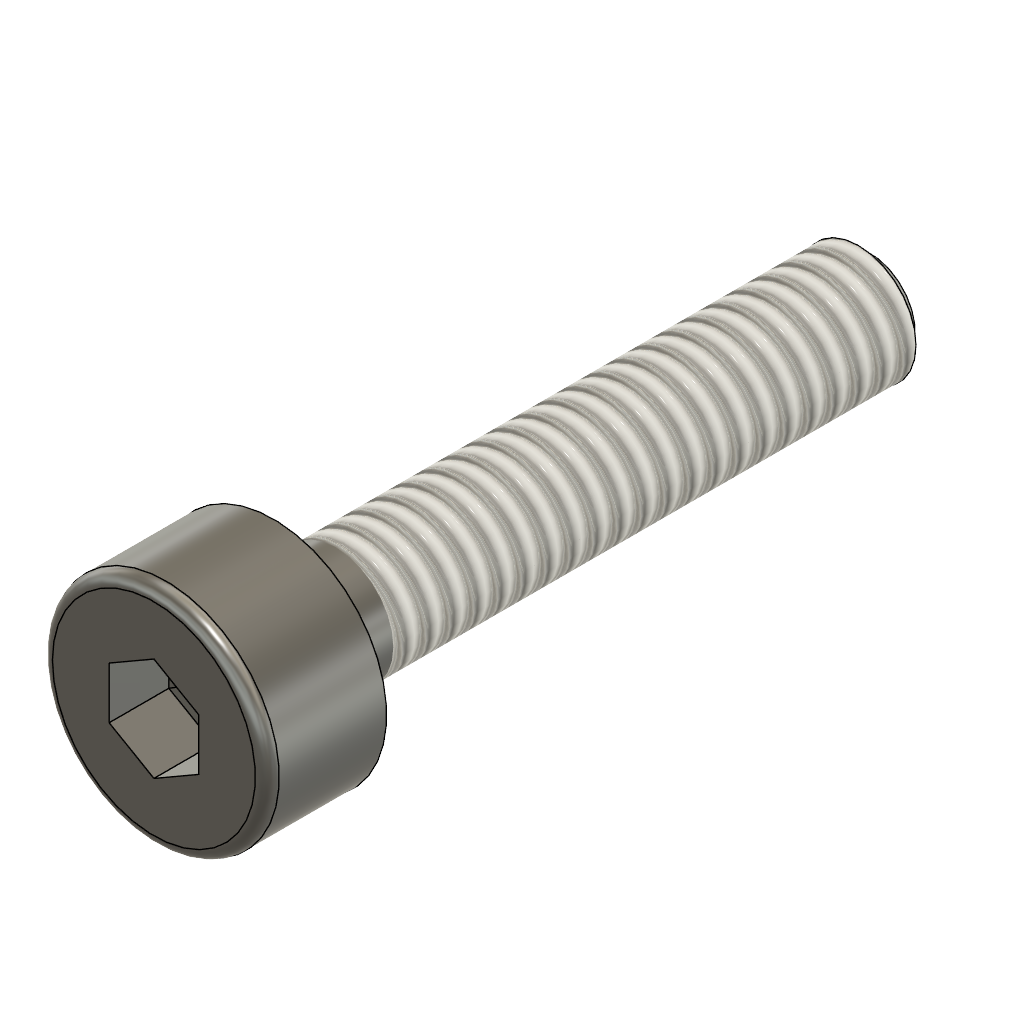
design "Zylinderschraube mit gestanztem Innensechskant ASME B18.3.1M - M2x0.4 x 10 Stahlklasse 2 Einfach"
description: Zylinderschraube mit gestanztem Innensechskant ASME B18.3.1M - M2x0.4 x 10
part number: BSHCS ASME B18.3.1M - M2x0.4 x 10 Stahlklasse 2 Einfach
Autodesk Fusion 360 part; units mm, degrees
sketch "Sketch1" plane through (0, 0, 0) normal (0, 1, 0) x (1, 0, 0)
  line L0 (-1, 0) -> (-1, 10)
  line L1 (-1, 10) -> (0, 10)
  line L2 (0, 10) -> (0, -2)
  line L3 (-1, 0) -> (-1.9, 0)
  line L4 (-1.9, 0) -> (-1.9, -2)
  line L5 (-1.9, -2) -> (0, -2)
  dimension "d101" = 10
  dimension "d102" = 2
  dimension "d109" = 3.8
  dimension "d110" = 2
  constraint perpendicular L0 L1
  constraint collinear origin L1.end L2.end
  constraint perpendicular L0 L3
  constraint coincident origin L3
  constraint vertical L2
  constraint coincident L2 L5.end
  constraint perpendicular L2 L5
  measures "d101" distance of origin L1
  measures "d102" distance of L3.end L5
revolve "Revolve1" add sketch "Sketch1" angle 360 about axis through (0, 0, -10) along (0, 0, 1)
ref_plane "WorkPlane1" through (0, 0, 2) normal (0, 0, 1) x (1, 0, 0)
sketch "Sketch6" plane through (0, 0, 2) normal (0, 0, 1) x (1, 0, 0)
  line L0 (0, -0.866) -> (0.75, -0.433)
  line L1 (0.75, -0.433) -> (0.75, 0.433)
  line L2 (0.75, 0.433) -> (0, 0.866)
  line L3 (0, 0.866) -> (-0.75, 0.433)
  line L4 (-0.75, 0.433) -> (-0.75, -0.433)
  line L5 (-0.75, -0.433) -> (0, -0.866)
  dimension "d111" = 1.5
  constraint vertical L1
  measures "d111" distance of L1 L4
extrude "Extrude1" cut sketch "Sketch6" against normal blind 1
extrude "Extrude2" cut 1 faces at (0, -0.2887, 1) along direction (0, 0, -1) blind 1 draft -85
thread "Thread3" "ANSI Metric M Profile 2.0 M2x0.4 M2x0.4 4g6g" major diameter 1.9335 minor diameter 1.4905 pitch 0.4 angle 60 resizes the face on face at (-0.9988, 0.0498, -6.6667) from (0, 0, -1.0454) to (0, 0, -10)
fillet "Fillet4" radius 0.2 1 edges at (-1.7714, 0.6871, 2)
sketch "Sketch7" plane through (0, 0, 0) normal (0, 1, 0) x (1, 0, 0)
  line L0 (-1.02, 10) -> (-1.02, 9.7546)
  line L1 (-1.02, 9.7546) -> (-0.7546, 10)
  line L2 (0, 10) -> (0, -2)
  line L3 (-1.02, 10) -> (0, 10)
  dimension "d104" = 0.7546
  dimension "d105" = 1.02
  dimension "d106" = 0.2454
  constraint coincident L2.start L3.end
  constraint perpendicular L2 L3
  constraint coincident L1.end L3
  constraint perpendicular L0 L3
  measures "d104" distance of L1.end L2
  measures "d105" distance of L0 L2.start
  measures "d106" distance of L0.end L3
revolve "Revolve3" cut sketch "Sketch7" angle 360 about axis through (0, 0, 1.75) along (0, 0, 1)
equation "adsk_nomlen = 10.00 mm"
equation "adsk_headh = 2.00 mm"
equation "adsk_headdia = 3.80 mm"
equation "adsk_nomdia = 2.00 mm"
equation "adsk_philwidth = 1.50 mm"
equation "d31 = -adsk_phildepth"
equation "adsk_phildepth = 1.00 mm"
equation "d71 = adsk_headh"
equation "d76 = -adsk_phildepth"
equation "adsk_thrlen = 8.95462 mm"
equation "d86 = adsk_nomdia * 0.1"
equation "adsk_startlen = 0.24538 mm"
equation "adsk_endpointdia = 1.50924 mm"
equation "d101 = adsk_nomlen"
equation "d102 = adsk_headh"
equation "d104 = adsk_endpointdia / 2"
equation "d105 = adsk_nomdia * 0.51"
equation "d106 = adsk_startlen"
equation "d108 = min(adsk_thrlen; adsk_nomlen - 0.001 mm)"
equation "d109 = adsk_headdia"
equation "d110 = adsk_nomdia"
equation "d111 = adsk_philwidth"

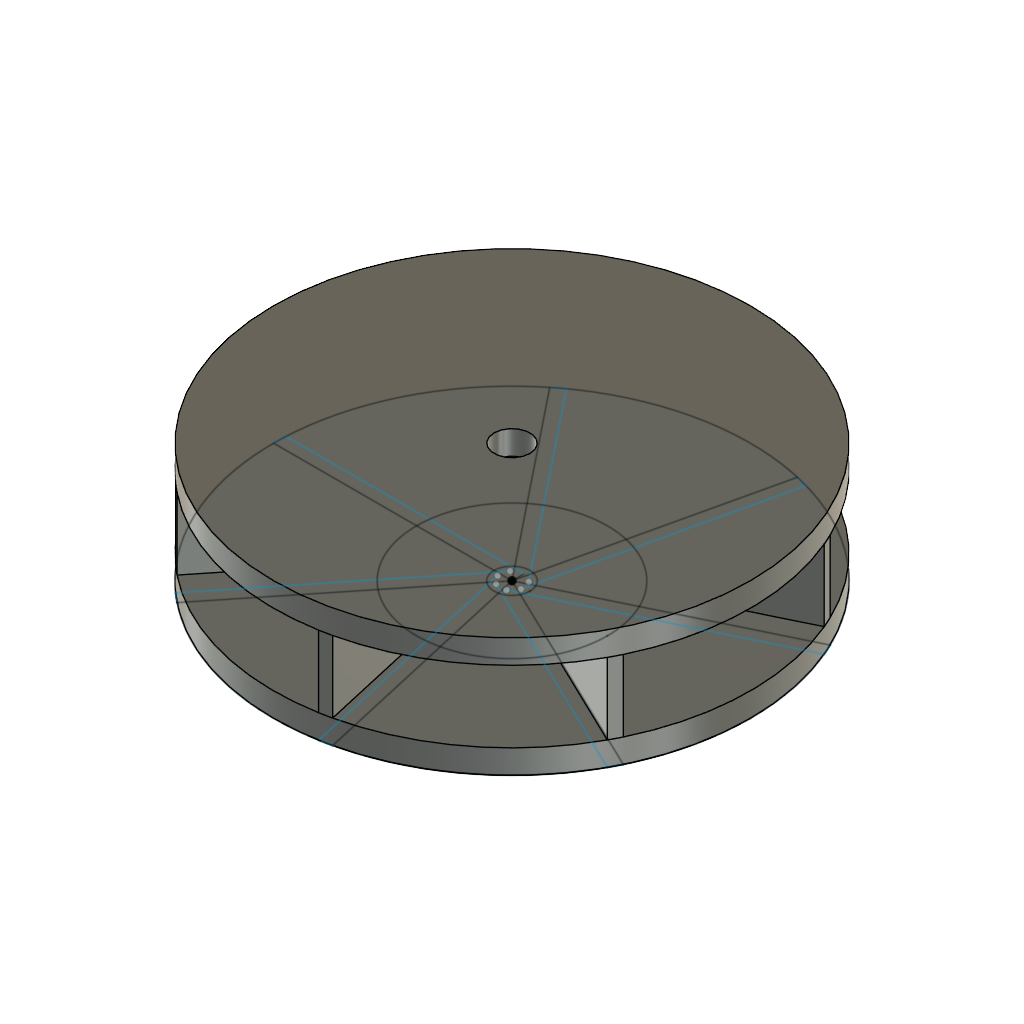
design "impellerneuimit ohne test"
Autodesk Fusion 360 part; units mm, degrees
sketch "Skizze1" plane through (0, 0, 0) normal (0, 0, 1) x (1, 0, 0)
  circle A0 centre (0, 0) radius 10
  line L0 (-10, 0) -> (0, 0)
  line L1 (0, 0) -> (0, 0.5)
  line L2 (0, 0.5) -> (-9.9875, 0.5)
  line L3 (-9.9875, 0.5) -> (-10, 0)
  circle A1 centre (0, 0) radius 4
  line L4 (-0.3909, 0.3117) -> (-6.618, -7.4968)
  line L5 (-6.2349, -7.8183) -> (0, 0)
  line L6 (-6.618, -7.4968) -> (-6.2349, -7.8183)
  line L7 (-0.4875, -0.1113) -> (1.735, -9.8483)
  line L8 (2.2252, -9.7493) -> (0, 0)
  line L9 (1.735, -9.8483) -> (2.2252, -9.7493)
  line L10 (-0.2169, -0.4505) -> (8.7815, -4.7839)
  line L11 (9.0097, -4.3388) -> (0, 0)
  line L12 (8.7815, -4.7839) -> (9.0097, -4.3388)
  line L13 (0.2169, -0.4505) -> (9.2154, 3.8829)
  line L14 (9.0097, 4.3388) -> (0, 0)
  line L15 (9.2154, 3.8829) -> (9.0097, 4.3388)
  line L16 (0.4875, -0.1113) -> (2.7099, 9.6258)
  line L17 (2.2252, 9.7493) -> (0, 0)
  line L18 (2.7099, 9.6258) -> (2.2252, 9.7493)
  line L19 (0.3909, 0.3117) -> (-5.8362, 8.1203)
  line L20 (-6.2349, 7.8183) -> (0, 0)
  line L21 (-5.8362, 8.1203) -> (-6.2349, 7.8183)
  circle A2 centre (0, 0) radius 0.75
  dimension "d1" = 20
  dimension "d2" = 8
  dimension "d4" = 360
  dimension "d12" = 1.5
  constraint coincident A0.centre L0.end
  constraint coincident A0 L0.start
  constraint horizontal L0
  constraint perpendicular L0 L1
  constraint coincident A0 L2.end
  constraint perpendicular L1 L2
  constraint concentric A0 A1
  measures "d1" diameter of A0
  measures "d2" diameter of A1
  measures "d12" diameter of A2
extrude "Extrusion1" add sketch "Skizze1" along normal blind 1 contours A0 A1 L11 L13 | A0 L15 | A1 L13 L14 L15 | A1 L10 L11 L12 | A0 L12 | A0 A1 L14 L16 | A0 A1 L8 L10 | A0 L18 | A1 L16 L17 L18 | A1 L7 L8 L9 | A0 L9 | A0 A1 L17 L19 | A0 A1 L5 L7 | A0 L21 | A1 L19 L20 L21 | A1 L4 L5 L6 | A0 L6 | A0 L2 A1 L20 | A0 L0 A1 L4 | A0 L3 | L0 L2 L3 A1
extrude "Extrusion2" add sketch "Skizze1" along normal blind 4 contours A1 L13 L14 L15 | A1 L10 L11 L12 | A1 L16 L17 L18 | A1 L7 L8 L9 | A1 L19 L20 L21 | A1 L4 L5 L6 | L0 L2 L3 A1
extrude "Extrusion3" add sketch "Skizze1" along normal blind 1 from surface at 4
extrude "Extrusion4" cut sketch "Skizze1" along normal blind 20 contours L11 L13 A2 | L11 L13 L14 A2 | L8 L10 L11 A2 | L14 L16 A2 | L8 L10 A2 | L14 L16 L17 A2 | L0 L4 L5 A2 | L1 L2 L20 | L5 L7 L8 A2 | L1 L2 L17 L19 L20 A2 | L0 L2 L20 A2 | L17 L19 A2 | L0 L4 A2 | L5 L7 A2 | L2 L20 A2
